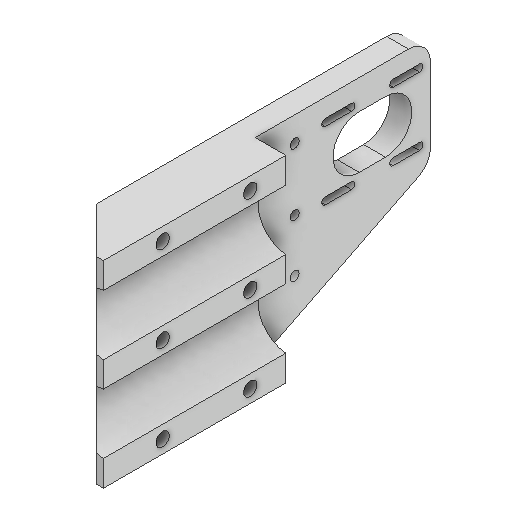
# Autodesk Inventor part: 3DP_PLA_Fiberglass_Pipe_Corner_Bracket_Clamp_and_B_axis_Stepper_Mount
Saved by Autodesk Inventor 2027 (Build 310192060, 192F)
## iProperties
Created: 2026-01-07
Part Number: 3DP_PLA_Fiberglass_Pipe_Corner_Bracket_Clamp_and_B_axis_Stepper_Mount
Material: Generic
Document SubType Name: Modeling
Designer: User
Density: 1 g/cm^3
Appearance: Default
Author: User
Autodesk Inventor part; units mm, degrees
ref_plane "YZ Plane" through (0, 0, 0) normal (1, 0, 0) x (0, 1, 0)
ref_plane "XZ Plane" through (0, 0, 0) normal (0, 1, 0) x (-1, 0, 0)
ref_plane "XY Plane" through (0, 0, 0) normal (0, 0, 1) x (1, 0, 0)
sketch "Sketch1" plane through (0, 0, 0) normal (0, 1, 0) x (-1, 0, 0)
  line L0 (0, 0) -> (100, 0)
  line L1 (0, 0) -> (0, 100)
  line L2 (100, 0) -> (0, 100)
  dimension "d0" = 100
  dimension "d1" = 100
  constraints: 6 end point
  measures "d0" distance of L0.start L1.end
  measures "d1" distance of L0.start L0.end
extrude "Extrusion1" add sketch "Sketch1" along normal blind 90
sketch "Sketch3" plane through (0, 90, 0) normal (0, 0, -1) x (-1, 0, 0)
  circle A0 centre (-1, -25.5) radius 13.75
  circle A1 centre (-1, -64.5) radius 13.75
  line L0 (0, -90) -> (0, 0) projected
  line L1 (0, 0) -> (100, 0) projected
  dimension "d11" = 90
  dimension "d12" = 27.5
  dimension "d13" = 27.5
  dimension "d14" = 39
  dimension "d63" = 1
  dimension "d64" = 1
  dimension "d65" = 25.5
  constraints: 2 centre point
  measures "d11" distance of L0.start L0.end
  measures "d12" diameter of A0
  measures "d13" diameter of A1
  measures "d14" distance of A1.centre A0.centre
  measures "d63" distance from line of L0 A0.centre
  measures "d64" distance from line of L0 A1.centre
  measures "d65" distance from line of L1 A0.centre
extrude "Extrusion3" cut sketch "Sketch3" against normal through all
sketch "Sketch4" plane through (0, 90, 0) normal (0, 1, 0) x (1, 0, 0)
  line L0 (-100, 0) -> (0, -100) projected
  line L1 (0, -100) -> (0, 0) projected
  line L2 (0, 0) -> (-100, 0) projected
  line L3 (-20, -80) -> (-20, -20)
  line L4 (-20, -20) -> (-80, -20)
  dimension "d18" = 20
  dimension "d19" = 20
  constraints: 4 end point, 2 point on line, 1 perpendicular, 1 vertical
  measures "d18" distance between parallel lines of L1 L3
  measures "d19" distance between parallel lines of L2 L4
extrude "Extrusion4" cut sketch "Sketch4" against normal blind 90 contours L4 L3 L0
sketch "Sketch6" plane through (-20, 90, 20) normal (-1, 0, 0) x (0, 0, 1)
  line L0 (80, -11.7864) -> (-20, -11.7864) projected
  line L1 (-20, -39.2136) -> (80, -39.2136) projected
  line L2 (80, -50.7864) -> (-20, -50.7864) projected
  line L3 (-20, -78.2136) -> (80, -78.2136) projected
  line L4 (60, -90) -> (0, -90) projected
  line L5 (60, 0) -> (60, -90) projected
  line L6 (0, -90) -> (0, 0) projected
  line L7 (0, 0) -> (60, 0) projected
  point P0 (-20, -90)
  point P1 (76, -11.7864)
  point P2 (76, -39.2136)
  point P3 (76, -50.7864)
  point P4 (76, -78.2136)
  point P5 (50, -84.125)
  point P6 (10, -84.125)
  point P7 (50, -45)
  point P8 (10, -45)
  point P9 (50, -5.875)
  point P10 (10, -5.875)
  dimension "d29" = 11.7864
  dimension "d32" = 5.875
  dimension "d34" = 11.5728
  dimension "d60" = 10
  dimension "d61" = 10
  dimension "d62" = 5.875
  dimension "d68" = 45
  constraints: 4 vertical alignment, 3 horizontal alignment
  measures "d29" distance between parallel lines of L4 L3
  measures "d32" distance from line of L4 point (50, -84.125)
  measures "d34" distance between parallel lines of L2 L1
  measures "d60" distance from line of L5 point (50, -84.125)
  measures "d61" distance from line of L6 point (10, -84.125)
  measures "d62" distance from line of L7 point (50, -5.875)
  measures "d68" distance from line of L4 point (50, -45)
hole "Hole1" at (-20, 5.875, 70) at (-20, 5.875, 30) at (-20, 45, 70) at (-20, 45, 30) at (-20, 84.125, 70) at (-20, 84.125, 30) direction (1, 0, 0) diameter 6.2 end through all
sketch "Sketch8" plane through (0, 78.2136, 0) normal (0, 0, -1) x (-1, 0, 0)
  line L0 (105, 34) -> (-10, 34)
  line L1 (-10, 34) -> (-10, -90)
  line L2 (-10, -90) -> (105, -90)
  line L3 (105, -90) -> (105, 34)
  point P0 (0, -78.2136)
  constraints: 8 end point, 2 parallel, 1 horizontal, 1 perpendicular
extrude "Extrusion6" cut sketch "Sketch8" against normal up to surface (20 mm away)
sketch "Sketch9" plane through (0, 0, 20) normal (0, 0, -1) x (-1, 0, 0)
  line L0 (0, 78.2136) -> (0, 90) projected
  arc A0 (0, 50.7864) -> (0, 78.2136) centre (-1, 64.5) ccw projected
  line L1 (0, 39.2136) -> (0, 50.7864) projected
  arc A1 (0, 11.7864) -> (0, 39.2136) centre (-1, 25.5) ccw projected
  line L2 (0, 0) -> (0, 11.7864) projected
  line L3 (20, 0) -> (0, 0) projected
  line L4 (20, 90) -> (20, 0) projected
  line L5 (0, 90) -> (20, 90) projected
  point P0 (0, 0)
extrude "Extrusion7" add sketch "Sketch9" along normal blind 6.25
sketch "Sketch10" plane through (-20, 0, 80) normal (-1, 0, 0) x (0, 0, 1)
  circle A0 centre (-50, 84.125) radius 3.1 projected
  circle A1 centre (-10, 84.125) radius 3.1 projected
  circle A2 centre (-50, 45) radius 3.1 projected
  circle A3 centre (-10, 45) radius 3.1 projected
  circle A4 centre (-50, 5.875) radius 3.1 projected
  circle A5 centre (-10, 5.875) radius 3.1 projected
  line L0 (-66.25, 90) -> (0, 90) projected
  line L1 (-66.25, 0) -> (-66.25, 90) projected
  line L2 (0, 0) -> (-66.25, 0) projected
  line L3 (0, 90) -> (0, 0) projected
  point P0 (-80, 0)
extrude "Extrusion8" add sketch "Sketch10" along normal blind 4
chamfer "Chamfer2" distance 4 angle 45 1 edges at (-24, 45, 80)
sketch "Sketch11" plane through (0, 0, 0) normal (0, -1, 0) x (1, 0, 0)
  line L0 (9, 97) -> (-33, 97)
  line L1 (-33, 97) -> (-33, 4)
  line L2 (-33, 4) -> (9, 4)
  line L3 (9, 4) -> (9, 97)
  line L4 (-24, 76) -> (0, 100) projected
  line L5 (-24, 13.75) -> (-24, 76) projected
  line L6 (0, 13.75) -> (-24, 13.75) projected
  line L7 (0, 100) -> (0, 13.75) projected
  point P0 (0, 0)
  dimension "d74" = 3
  constraints: 8 end point, 2 parallel, 1 horizontal, 1 perpendicular
  measures "d74" distance from line of L0 L4.end
extrude "Extrusion9" cut sketch "Sketch11" against normal through all contours L3 L2 L1 L0 L4 L5 L6 L7 | L7 L6 L5 L4 L0 keep common part
sketch "Sketch12" plane through (0, 0, 13.75) normal (0, 0, -1) x (-1, 0, 0)
  line L0 (0, 50.7864) -> (0, 39.2136) projected
  arc A0 (0, 11.7864) -> (0, 39.2136) centre (-1, 25.5) ccw projected
  line L1 (0, 11.7864) -> (0, 0) projected
  line L2 (0, 0) -> (24, 0) projected
  line L3 (24, 90) -> (24, 0) projected
  line L4 (0, 90) -> (24, 90) projected
  line L5 (0, 90) -> (0, 78.2136) projected
  arc A1 (0, 50.7864) -> (0, 78.2136) centre (-1, 64.5) ccw projected
  line L6 (14, 90) -> (14, 0)
  point P0 (0, 0)
  dimension "d77" = 10
  constraints: 2 end point, 2 point on line, 1 perpendicular
  measures "d77" distance between parallel lines of L3 L6
extrude "Extrusion10" add sketch "Sketch12" along normal blind 80 contours L4 L3 L2 L6
sketch "Sketch13" plane through (-14, 0, 13.75) normal (1, 0, 0) x (0, 0, -1)
  line L0 (0, 0) -> (0, 90) projected
  line L1 (0, 0) -> (80, 0) projected
  line L2 (80, 90) -> (80, 0) projected
  line L3 (0, 90) -> (80, 90) projected
  line L4 (0, 64.5) -> (80, 64.5)
  circle A0 centre (53.5, 64.5) radius 9.165
  circle A1 centre (18, 50.3) radius 7
  circle A2 centre (18, 78.7) radius 7
  line L5 (59.5, 64.5) -> (47.5, 64.5) construction
  line L6 (59.5, 76.5) -> (47.5, 76.5)
  line L7 (47.5, 52.5) -> (59.5, 52.5)
  arc A3 (59.5, 52.5) -> (59.5, 76.5) centre (59.5, 64.5) ccw
  arc A4 (47.5, 76.5) -> (47.5, 52.5) centre (47.5, 64.5) ccw
  line L8 (44, 49) -> (32, 49) construction
  line L9 (44, 50.6) -> (32, 50.6)
  line L10 (32, 47.4) -> (44, 47.4)
  arc A5 (44, 47.4) -> (44, 50.6) centre (44, 49) ccw
  arc A6 (32, 50.6) -> (32, 47.4) centre (32, 49) ccw
  line L11 (44, 80) -> (32, 80) construction
  line L12 (44, 81.6) -> (32, 81.6)
  line L13 (32, 78.4) -> (44, 78.4)
  arc A7 (44, 78.4) -> (44, 81.6) centre (44, 80) ccw
  arc A8 (32, 81.6) -> (32, 78.4) centre (32, 80) ccw
  line L14 (75, 49) -> (63, 49) construction
  line L15 (75, 50.6) -> (63, 50.6)
  line L16 (63, 47.4) -> (75, 47.4)
  arc A9 (75, 47.4) -> (75, 50.6) centre (75, 49) ccw
  arc A10 (63, 50.6) -> (63, 47.4) centre (63, 49) ccw
  line L17 (63, 80) -> (75, 80) construction
  line L18 (63, 78.4) -> (75, 78.4)
  line L19 (75, 81.6) -> (63, 81.6)
  arc A11 (63, 81.6) -> (63, 78.4) centre (63, 80) ccw
  arc A12 (75, 78.4) -> (75, 81.6) centre (75, 80) ccw
  circle A13 centre (18, 50.3) radius 2.1
  circle A14 centre (18, 78.7) radius 2.1
  point P0 (13.75, 0)
  point P1 (38, 49)
  point P2 (38, 80)
  point P3 (69, 49)
  point P4 (69, 80)
  dimension "d80" = 25.5
  dimension "d81" = 18.33
  dimension "d82" = 14
  dimension "d83" = 14
  dimension "d84" = 18
  dimension "d85" = 14.2
  dimension "d86" = 14.2
  dimension "d87" = 53.5
  dimension "d88" = 6
  dimension "d89" = 24
  dimension "d90" = 6
  dimension "d91" = 3.2
  dimension "d92" = 6
  dimension "d93" = 3.2
  dimension "d94" = 6
  dimension "d95" = 3.2
  dimension "d96" = 3.2
  dimension "d97" = 6
  dimension "d98" = 15.5
  dimension "d99" = 15.5
  dimension "d100" = 15.5
  dimension "d101" = 15.5
  dimension "d102" = 4.2
  dimension "d103" = 4.2
  constraints: 42 end point, 20 point on circle, 20 tangent, 15 centre point, 8 point on line, 6 parallel, 5 midpoint, 3 vertical alignment, 2 coincident, 1 horizontal, 1 perpendicular
  measures "d80" distance between parallel lines of L3 L4
  measures "d81" diameter of A0
  measures "d82" diameter of A1
  measures "d83" diameter of A2
  measures "d84" distance from line of L0 A2.centre
  measures "d85" vertical distance of A0.centre A1.centre
  measures "d86" vertical distance of A0.centre A2.centre
  measures "d87" distance from line of L0 A0.centre
  measures "d88" distance of A0.centre L5.end
  measures "d89" diameter of A4
  measures "d90" distance of point (38, 49) L8.end
  measures "d91" diameter of A6
  measures "d92" distance of point (38, 80) L11.end
  measures "d93" diameter of A8
  measures "d94" distance of point (69, 49) L14.end
  measures "d95" diameter of A10
  measures "d96" diameter of A12
  measures "d97" distance of L17.end point (69, 80)
  measures "d98" horizontal distance of A0.centre point (38, 49)
  measures "d99" horizontal distance of point (38, 80) A0.centre
  measures "d100" horizontal distance of point (38, 49) A0.centre
  measures "d101" horizontal distance of point (69, 49) A0.centre
  measures "d102" diameter of A13
  measures "d103" diameter of A14
extrude "Extrusion11" cut sketch "Sketch13" against normal through all contours A4 L6 A3 L4 A0 | L4 A0 A3 L7 A4 | A0 L4 | L4 A0 | A5 L10 A6 L9 | A7 L13 A8 L12 | A9 L16 A10 L15 | A11 L19 A12 L18 | A13 | A14
chamfer "Chamfer3" distance 40 distance2 80 1 edges at (-19, 0, -66.25) measured on face at (-17.3333, 60, -66.25)
fillet "Fillet1" radius 10 2 edges at (-19, 40, -66.25) (-19, 90, -66.25)
sketch "Sketch14" plane through (-24, 0, 80) normal (-1, 0, 0) x (0, 0, 1)
  circle A0 centre (-84.25, 50.3) radius 2.1 projected
  point P0 (-80, 0)
  point P1 (-84.25, 26.3)
  dimension "d110" = 24
  measures "d110" distance of point (-84.25, 26.3) A0.centre
hole "Hole3" at (-24, 26.3, -4.25) direction (1, 0, 0) diameter 4.2 end through all
equation "\"d0\" = d1"
equation "\"d64\" = d63"
equation "\"d19\" = d18"
equation "\"d86\" = d85"
equation "\"d99\" = d98"
equation "\"d100\" = d98"
equation "\"d101\" = d100"
body "Solid1"
